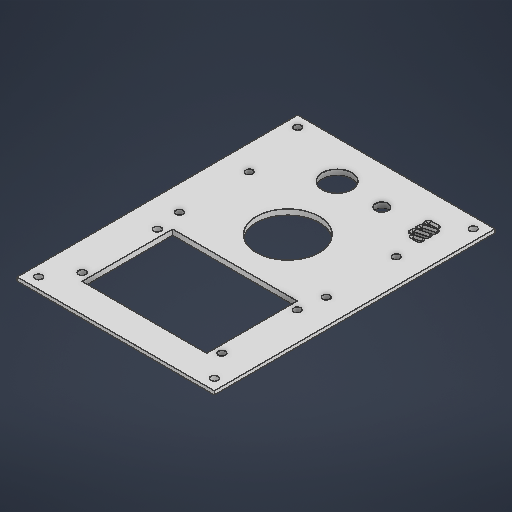
# Autodesk Inventor part: top
Saved by Autodesk Inventor 2026.2 (Build 302298010, 298A)
## iProperties
Created: 2026-05-12
Part Number: top
Material: 일반
Document SubType Name: Modeling
Designer: work
Density: 1 g/cm^3
Appearance: 기본값
Author: work
Autodesk Inventor part; units mm, degrees
ref_plane "YZ Plane" through (0, 0, 0) normal (1, 0, 0) x (0, 1, 0)
ref_plane "XZ Plane" through (0, 0, 0) normal (0, 1, 0) x (-1, 0, 0)
ref_plane "XY Plane" through (0, 0, 0) normal (0, 0, 1) x (1, 0, 0)
sketch "스케치1" plane through (0, 0, 0) normal (0, 1, 0) x (-1, 0, 0)
  line L0 (0, 0) -> (110, 0)
  line L1 (110, 0) -> (110, -156.5)
  line L2 (110, -156.5) -> (0, -156.5)
  line L3 (0, -156.5) -> (0, 0)
  line L4 (6, -6) -> (104, -6) construction
  line L5 (104, -6) -> (104, -150.5) construction
  line L6 (104, -150.5) -> (6, -150.5) construction
  line L7 (6, -150.5) -> (6, -6) construction
  line L8 (110, -78.25) -> (0, -78.25) construction
  line L9 (55, -156.5) -> (55, 0) construction
  line L10 (22, -129.5) -> (15, -129.5)
  line L11 (15, -129.5) -> (15, -141.5)
  line L12 (15, -141.5) -> (22, -141.5)
  line L13 (22, -141.5) -> (22, -129.5)
  line L14 (21.1476, -129.5) -> (15, -131.1472)
  line L15 (22, -131.3421) -> (15, -133.2178)
  line L16 (22, -133.4127) -> (15, -135.2883)
  line L17 (22, -135.4833) -> (15, -137.3589)
  line L18 (22, -137.5538) -> (15, -139.4294)
  line L19 (22, -139.6244) -> (15, -141.5)
  circle A0 centre (6, -150.5) radius 2
  circle A1 centre (104, -150.5) radius 2
  circle A2 centre (104, -6) radius 2
  circle A3 centre (6, -6) radius 2
  circle A4 centre (42, -135.5) radius 3.5
  line L20 (18.3244, -135.5) -> (104, -135.5) construction
  circle A5 centre (67, -135.5) radius 8.25
  line L21 (18.5, -129.5) -> (18.5, -78.25) construction
  line L22 (14, -76.5) -> (96, -76.5) construction
  line L23 (96, -76.5) -> (96, -115.5) construction
  line L24 (96, -115.5) -> (14, -115.5) construction
  line L25 (14, -115.5) -> (14, -76.5) construction
  line L26 (55, -76.5) -> (55, -115.5) construction
  line L27 (96, -96) -> (14, -96) construction
  circle A6 centre (55, -96) radius 17.5
  circle A7 centre (96, -76.5) radius 2
  circle A8 centre (96, -115.5) radius 2
  circle A9 centre (14, -115.5) radius 2
  circle A10 centre (14, -76.5) radius 2
  line L28 (20.25, -16) -> (89.75, -16)
  line L29 (89.75, -16) -> (89.75, -66.5)
  line L30 (89.75, -66.5) -> (20.25, -66.5)
  line L31 (20.25, -66.5) -> (20.25, -16)
  line L32 (89.75, -41.25) -> (20.25, -41.25) construction
  line L33 (55, -16) -> (55, -66.5) construction
  line L34 (16, -20.25) -> (94, -20.25) construction
  line L35 (94, -20.25) -> (94, -62.25) construction
  line L36 (94, -62.25) -> (16, -62.25) construction
  line L37 (16, -62.25) -> (16, -20.25) construction
  line L38 (16, -20.25) -> (94, -62.25) construction
  line L39 (94, -20.25) -> (16, -62.25) construction
  circle A11 centre (94, -20.25) radius 2
  circle A12 centre (94, -62.25) radius 2
  circle A13 centre (16, -62.25) radius 2
  circle A14 centre (16, -20.25) radius 2
  point P0 (104, -78.25)
  point P1 (55, -150.5)
  point P2 (18.5, -141.5)
  point P3 (55, -41.25)
  dimension "d0" = 6
  dimension "d1" = 6
  dimension "d2" = 7
  dimension "d3" = 12
  dimension "d4" = 2
  dimension "d6" = 2
  dimension "d7" = 2
  dimension "d8" = 75
  dimension "d9" = 2
  dimension "d10" = 2
  dimension "d11" = 15
  dimension "d12" = 15
  dimension "d13" = 4
  dimension "d14" = 4
  dimension "d15" = 4
  dimension "d16" = 4
  dimension "d17" = 7
  dimension "d18" = 15
  dimension "d19" = 20
  dimension "d20" = 16.5
  dimension "d21" = 25
  dimension "d26" = 82
  dimension "d27" = 39
  dimension "d28" = 35
  dimension "d29" = 4
  dimension "d30" = 4
  dimension "d31" = 4
  dimension "d32" = 4
  dimension "d33" = 69.5
  dimension "d34" = 50.5
  dimension "d35" = 78
  dimension "d36" = 42
  dimension "d37" = 4
  dimension "d38" = 4
  dimension "d39" = 4
  dimension "d40" = 4
  dimension "d42" = 10
  dimension "d44" = 10
  dimension "d45" = 10
  dimension "d46" = 20
  constraints: 80 end point, 20 midpoint, 19 point on line, 18 parallel, 15 centre point, 13 coincident, 7 perpendicular, 6 horizontal
  measures "d0" distance between parallel lines of L1 L5
  measures "d1" distance between parallel lines of L2 L6
  measures "d2" distance between parallel lines of L11 L13
  measures "d3" distance between parallel lines of L10 L12
  measures "d4" distance between parallel lines of L19 L18
  measures "d6" distance between parallel lines of L14 L15
  measures "d7" distance between parallel lines of L17 L16
  measures "d8" angle of L11 L18
  measures "d9" distance between parallel lines of L18 L17
  measures "d10" distance between parallel lines of L15 L16
  measures "d11" distance from line of L3 L11.end
  measures "d12" distance from line of L2 point (18.5, -141.5)
  measures "d13" diameter of A0
  measures "d14" diameter of A1
  measures "d15" diameter of A2
  measures "d16" diameter of A3
  measures "d17" diameter of A4
  measures "d18" distance between parallel lines of L6 L20
  measures "d19" distance from line of L13 A4.centre
  measures "d20" diameter of A5
  measures "d21" distance of A5.centre A4.centre
  measures "d26" distance of L23.end L24.end
  measures "d27" distance of L22.end L23.end
  measures "d28" diameter of A6
  measures "d29" diameter of A7
  measures "d30" diameter of A8
  measures "d31" diameter of A9
  measures "d32" diameter of A10
  measures "d33" distance of L29.end L30.end
  measures "d34" distance of L28.end L29.end
  measures "d35" distance of L35.end L36.end
  measures "d36" distance of L34.end L35.end
  measures "d37" diameter of A11
  measures "d38" diameter of A12
  measures "d39" diameter of A13
  measures "d40" diameter of A14
  measures "d42" distance between parallel lines of L28 L4
  measures "d44" distance between parallel lines of L35 L5
  measures "d45" distance between parallel lines of L30 L22
  measures "d46" distance between parallel lines of L20 L24
extrude "돌출1" add sketch "스케치1" along normal blind 3 contours L0 L1 L2 L3 | L13 L15 L11 L14 L10 | L13 L17 L11 L16 | L13 L19 L11 L18
fillet "모깎기1" radius 0.25 14 edges at (-22, 1.5, -137.5538) (-15, 1.5, -137.3589) (-15, 1.5, -133.2178) (-22, 1.5, -141.5) (-15, 1.5, -141.5) (-22, 1.5, -131.3421) (-22, 1.5, -139.6244) (-22, 1.5, -133.4127) (-21.1476, 1.5, -129.5) (-15, 1.5, -129.5) (-15, 1.5, -131.1472) (-15, 1.5, -135.2883) (-15, 1.5, -139.4294) (-22, 1.5, -135.4833)
chamfer "모따기1" distance 1 angle 45 28 edges at (-19.4965, 3, -129.7174) (-17.2493, 3, -129.5) (-15.0732, 3, -129.5732) (-15, 3, -130.2857) (-15.0978, 3, -131.0198) (-17.314, 3, -130.5272) (-18.4353, 3, -132.2973) (-21.9022, 3, -131.4696) (-22, 3, -132.4444) (-21.9483, 3, -133.3731) (-18.5647, 3, -134.3332) (-15.0978, 3, -135.1609) (-15, 3, -134.1861) (-15.0517, 3, -133.2574) (-21.9022, 3, -135.6107) (-18.4353, 3, -136.4384) (-15.0517, 3, -137.3985) (-15, 3, -138.3272) (-15.0978, 3, -139.302) (-18.5647, 3, -138.4743) (-21.9483, 3, -137.5142) (-22, 3, -136.5855) (-22, 3, -140.6001) (-21.9268, 3, -141.4268) (-19.3245, 3, -141.5) (-16.6511, 3, -141.2826) (-19.2598, 3, -140.3586) (-21.9022, 3, -139.7518)
chamfer "모따기2" distance 1 angle 45 4 edges at (0, 0, -78.25) (-55, 0, 0) (-110, 0, -78.25) (-55, 0, -156.5)
